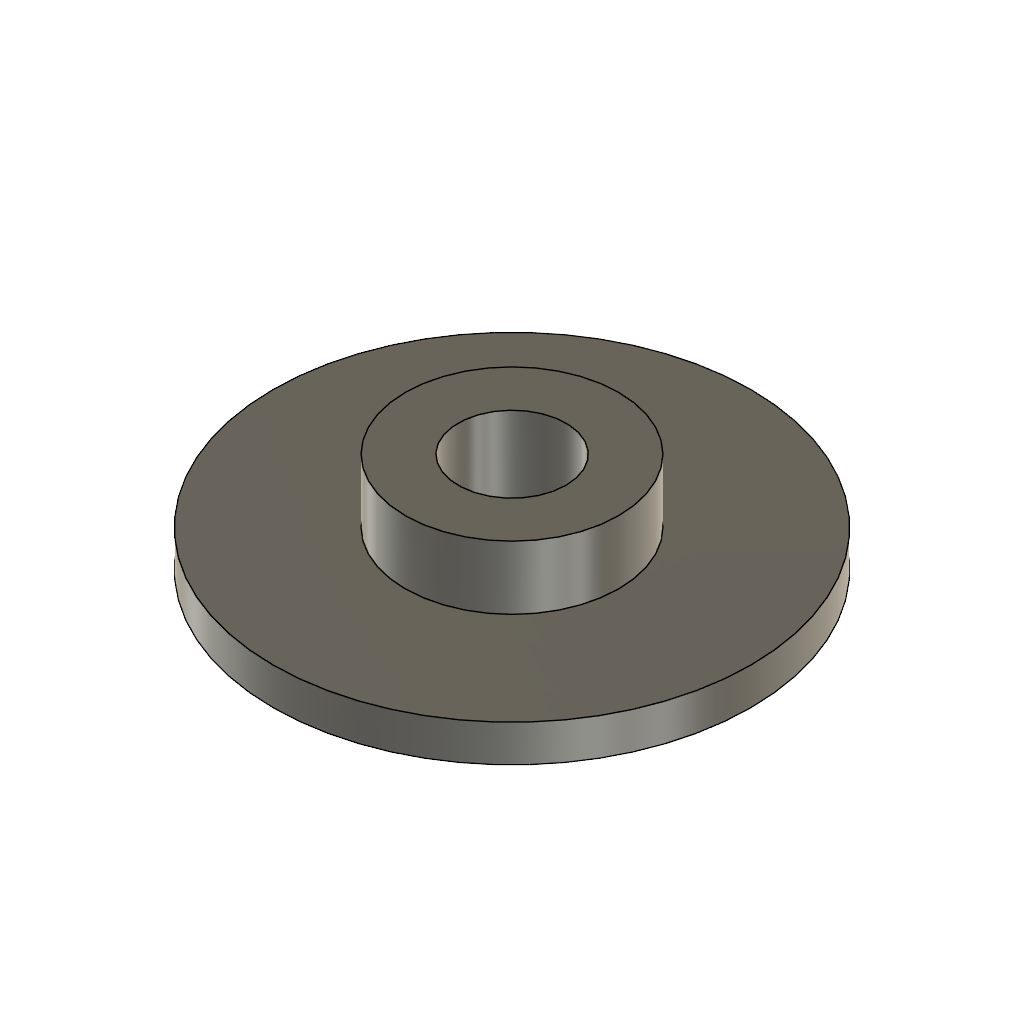
mce401_mic_mount (Autodesk Fusion 360 design; units mm, degrees)
Autodesk Fusion 360 part; units mm, degrees
sketch "Skizze1" plane through (0, 0, 0) normal (0, 0, 1) x (1, 0, 0)
  circle A0 centre (0, 0) radius 22.6
  dimension "d1" = 45.2
  constraint coincident A0.centre origin
  measures "d1" diameter of A0
extrude "Extrusion1" add sketch "Skizze1" along normal blind 3.5
sketch "Skizze2" plane through (0, 0, 3.5) normal (0, 0, 1) x (-1, 0, 0)
  circle A0 centre (0, 0) radius 22.6
  circle A1 centre (0, 0) radius 10.1
  dimension "d4" = 20.2
  constraint coincident A0.centre A1.centre
  measures "d4" diameter of A1
extrude "Extrusion2" add sketch "Skizze2" along normal blind 6 contours A1
hole "Bohrung1" at (0.018, -0.0085, 9.5) direction (0, 0, -1) diameter 10.2 depth 8.5 tip angle 180
hole "Bohrung2" at (0, 0, 0) direction (0, 0, 1) diameter 8 depth 12 tip angle 180
